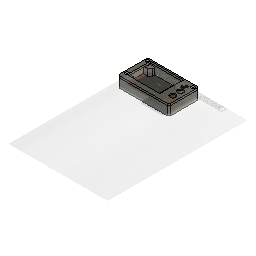
TFT screen (Autodesk Fusion 360 design; units mm, degrees)
part number: 2025-12-18-20-07-08-891
Autodesk Fusion 360 part; units mm, degrees
sketch "Sketch1" plane through (0, 0, 0) normal (0, 0, 1) x (1, 0, 0)
  line L0 (0, 0) -> (108, 0)
  line L1 (108, 0) -> (108, 63)
  line L2 (108, 63) -> (0, 63)
  line L3 (0, 63) -> (0, 0)
  line L4 (0, 0) -> (3, 0) construction
  line L5 (3, 0) -> (3, 3) construction
  line L6 (3, 3) -> (105, 3)
  line L7 (105, 3) -> (105, 60)
  line L8 (105, 60) -> (3, 60)
  line L9 (3, 60) -> (3, 3)
  line L10 (105, 60) -> (86, 60)
  line L11 (86, 60) -> (86, 3)
  line L12 (86, 3) -> (105, 3)
  line L13 (105, 3) -> (105, 60)
  line L14 (3, 60) -> (18, 60)
  line L15 (18, 60) -> (18, 3)
  line L16 (18, 3) -> (3, 3)
  line L17 (3, 3) -> (3, 60)
  line L18 (3, 60) -> (6, 60)
  line L19 (3, 60) -> (6, 60)
  line L20 (6, 60) -> (6, 57) construction
  circle A0 centre (6, 57) radius 1.6
  line L21 (3, 60) -> (3, 10) construction
  line L22 (3, 10) -> (6, 10) construction
  line L23 (6, 10) -> (6, 13) construction
  circle A1 centre (6, 13) radius 1.6
  line L24 (105, 60) -> (72.5, 60) construction
  line L25 (72.5, 60) -> (62.5, 60)
  line L26 (62.5, 60) -> (62.5, 38)
  line L27 (62.5, 38) -> (72.5, 38)
  line L28 (72.5, 38) -> (72.5, 60)
  line L29 (57.6, 60) -> (18, 60)
  line L30 (18, 60) -> (18, 3)
  line L31 (18, 3) -> (57.6, 3)
  line L32 (57.6, 3) -> (57.6, 60)
  dimension "d1" = 108
  dimension "d2" = 63
  dimension "d3" = 102
  dimension "d4" = 57
  dimension "d5" = 19
  dimension "d12" = 15
  dimension "d15" = 3.2
  dimension "d16" = 50
  dimension "d17" = 3
  dimension "d18" = 3
  dimension "d19" = 3.2
  dimension "d23" = 32.5
  dimension "d24" = 10
  dimension "d25" = 22
  constraint horizontal L0
  constraint vertical L1
  constraint horizontal L2
  constraint vertical L3
  constraint coincident L0.start L3.end
  constraint coincident L0 L4.end
  constraint perpendicular L4 L5
  constraint horizontal L6
  constraint vertical L7
  constraint horizontal L8
  constraint vertical L9
  constraint horizontal L10
  constraint vertical L11
  constraint horizontal L12
  constraint vertical L13
  constraint horizontal L14
  constraint vertical L15
  constraint horizontal L16
  constraint vertical L17
  constraint coincident L8 L18.end
  constraint perpendicular L8 L20
  constraint coincident L20.end A0.centre
  constraint perpendicular L8 L21
  constraint perpendicular L21 L22
  constraint perpendicular L22 L23
  constraint coincident L23.end A1.centre
  constraint perpendicular L11 L24
  constraint horizontal L25
  constraint vertical L26
  constraint horizontal L27
  constraint vertical L28
  constraint horizontal L29
  constraint vertical L30
  constraint horizontal L31
  constraint vertical L32
  constraint coincident L8 L29.start
  measures "d1" distance of L0.start L0.end
  measures "d2" distance of L0.start L2.end
  measures "d3" distance of L5.end L6.end
  measures "d4" distance of L5.end L8.end
  measures "d5" distance of L7.end L10.end
  measures "d12" distance of L8.end L14.end
  measures "d15" diameter of A0
  measures "d16" distance of L8.end L21.end
  measures "d17" distance of L21.end L22.end
  measures "d18" distance of L22.end L23.end
  measures "d19" diameter of A1
  measures "d23" distance of L7.end L24.end
  measures "d24" distance of L24.end L25.end
  measures "d25" distance of L24.end L27.end
extrude "Extrude1" add sketch "Sketch1" against normal blind 4 contours L0 L1 L2 L3 | L6 L8 L9 L14 L15 L16 L17 L18 L19 L30 | L6 L8 L15 L29 L30 L31 L32 | L6 L8 L11 L26 L27 L28 L32 | L6 L7 L8 L10 L11 L12 L13 | L8 L25 L26 L27 L28 | A0 | A1 makes body 1
extrude "Extrude2" add sketch "Sketch1" along normal blind 19 contours L0 L1 L2 L3 bodies 1
extrude "Extrude3" add sketch "Sketch1" along normal blind 6 contours L6 L7 L8 L10 L11 L12 L13 bodies 1
extrude "Extrude4" add sketch "Sketch1" along normal blind 12 contours L6 L8 L9 L14 L15 L16 L17 L18 L19 L30 | A0 | A1 bodies 1
extrude "Extrude5" cut sketch "Sketch1" along normal blind 3 from surface at 9 contours A0 | A1 bodies 1
extrude "Extrude6" cut sketch "Sketch1" against normal blind 2 contours L8 L25 L26 L27 L28 bodies 1
sketch "Sketch2" plane through (0, 60, 0) normal (0, -1, 0) x (1, 0, 0)
  line L0 (18, 12) -> (18, 0)
  line L1 (18, 0) -> (62.5, 0)
  line L2 (62.5, 0) -> (62.5, -2)
  line L3 (62.5, -2) -> (72.5, -2)
  line L4 (72.5, -2) -> (72.5, 0)
  line L5 (72.5, 0) -> (86, 0)
  line L6 (86, 0) -> (86, 6)
  line L7 (86, 6) -> (105, 6)
  line L8 (105, 6) -> (105, 19)
  line L9 (105, 19) -> (3, 19)
  line L10 (3, 19) -> (3, 12)
  line L11 (3, 12) -> (18, 12)
  line L12 (62.5, -2) -> (72.5, -2)
  line L13 (72.5, -2) -> (72.5, 2.5)
  line L14 (72.5, 2.5) -> (62.5, 2.5)
  line L15 (62.5, 2.5) -> (62.5, -2)
  point P0 (72.5, 0)
  dimension "d28" = 4.5
  constraint horizontal L12
  constraint vertical L13
  constraint horizontal L14
  constraint vertical L15
  constraint coincident L2.end L3.start
  constraint coincident P0 L13
  measures "d28" distance of L2.end L14.end
extrude "Extrude7" cut sketch "Sketch2" against normal blind 3 contours L2 L3 L4 L12 L13 L14 L15 bodies 1
fillet "Fillet1" radius 1 4 edges at (62.5, 61.5, 2.5) (72.5, 61.5, 2.5) (62.5, 50.5, -2) (72.5, 50.5, -2) on bodies 1
extrude "Extrude8" cut sketch "Sketch1" against normal blind 2 contours L6 L8 L15 L29 L30 L31 L32 bodies 1
fillet "Fillet2" radius 1 2 edges at (57.6, 31.5, 0) (57.6, 31.5, -2) on bodies 1
sketch "Sketch3" plane through (0, 0, 12) normal (0, 0, 1) x (-1, 0, 0)
  circle A0 centre (-6, -57) radius 1.6
  circle A1 centre (-6, -13) radius 1.6
  line L0 (-3, -3) -> (-18, -3)
  line L1 (-18, -3) -> (-18, -60)
  line L2 (-18, -60) -> (-3, -60)
  line L3 (-3, -60) -> (-3, -3)
  line L4 (-18, -20.2) -> (-3, -20.2)
  line L5 (-3, -20.2) -> (-3, -50.2)
  line L6 (-3, -50.2) -> (-18, -50.2)
  line L7 (-18, -50.2) -> (-18, -20.2)
  dimension "d37" = 30
  constraint horizontal L4
  constraint vertical L5
  constraint horizontal L6
  constraint vertical L7
  constraint coincident L1 L4.start
  measures "d37" distance of L4.start L6.end
extrude "Extrude9" cut sketch "Sketch3" against normal blind 14 contours L1 L3 L4 L5 L6 L7 bodies 1
chamfer "Chamfer1" distance 5 angle 45 2 edges at (18, 50.2, 5) (18, 20.2, 5) on bodies 1
chamfer "Chamfer2" distance 2 angle 45 1 edges at (86, 31.5, 6) on bodies 1
sketch "Sketch4" plane through (0, 0, 19) normal (0, 0, 1) x (-1, 0, 0)
  line L0 (-105, -60) -> (-105, -3)
  line L1 (-105, -3) -> (-3, -3)
  line L2 (-3, -3) -> (-3, -60)
  line L3 (-3, -60) -> (-105, -60)
  line L4 (0, -63) -> (0, 0)
  line L5 (0, 0) -> (-108, 0)
  line L6 (-108, 0) -> (-108, -63)
  line L7 (-108, -63) -> (0, -63)
  line L8 (-3, -60) -> (-9, -60)
  line L9 (-9, -60) -> (-78.5, -60)
  line L10 (-78.5, -60) -> (-78.5, -10)
  line L11 (-78.5, -10) -> (-9, -10)
  line L12 (-9, -10) -> (-9, -60)
  line L13 (-9, -60) -> (-3, -60)
  line L14 (-3, -60) -> (-3, -3)
  line L15 (-3, -3) -> (-9, -3)
  line L16 (-9, -3) -> (-9, -60)
  line L17 (-3, -9.5) -> (-3, -60)
  circle A0 centre (-6, -57) radius 1.6
  dimension "d42" = 6
  dimension "d43" = 69.5
  dimension "d81" = 50
  constraint coincident L2.end L3.start
  constraint perpendicular L2 L8
  constraint horizontal L9
  constraint vertical L10
  constraint horizontal L11
  constraint vertical L12
  constraint horizontal L13
  constraint vertical L14
  constraint horizontal L15
  constraint vertical L16
  constraint coincident L1.end L2.start
  constraint coincident L8 L2.end
  constraint vertical L17
  measures "d42" distance of L2.end L8.end
  measures "d43" distance of L8.end L9.end
  measures "d81" distance of L9.end L10.end
extrude "Extrude10" add sketch "Sketch4" against normal blind 2 separate body contours L0 L1 L3 L10 L11 L16 | L1 L2 L3 L8 L12 L13 L14 L15 L16 L17 | A0 makes body 2
extrude "Extrude11" add sketch "Sketch4" against normal blind 4 contours L1 L2 L3 L8 L12 L13 L14 L15 L16 L17 | A0 bodies 2
sketch "Sketch5" plane through (0, 0, 19) normal (0, 0, 1) x (-1, 0, 0)
  line L0 (-105, -60) -> (-105, -3)
  line L1 (-105, -3) -> (-3, -3)
  line L2 (-3, -3) -> (-3, -60)
  line L3 (-3, -60) -> (-105, -60)
  line L4 (0, -63) -> (0, 0)
  line L5 (0, 0) -> (-108, 0)
  line L6 (-108, 0) -> (-108, -63)
  line L7 (-108, -63) -> (0, -63)
  circle A0 centre (-6, -57) radius 1.8
  circle A1 centre (-6, -13) radius 1.8
  dimension "d49" = 3.6
  dimension "d50" = 3.6
  measures "d49" diameter of A0
  measures "d50" diameter of A1
extrude "Extrude12" cut sketch "Sketch5" against normal blind 4 contours A0 | A1 bodies 2
sketch "Sketch6" plane through (0, 0, 19) normal (0, 0, 1) x (-1, 0, 0)
  circle A0 centre (-6, -13) radius 1.8
  circle A1 centre (-6, -57) radius 1.8
  line L0 (-3, -3) -> (-105, -3)
  line L1 (-105, -3) -> (-105, -60)
  line L2 (-105, -60) -> (-78.5, -60)
  line L3 (-78.5, -60) -> (-78.5, -10)
  line L4 (-78.5, -10) -> (-9, -10)
  line L5 (-9, -10) -> (-9, -60)
  line L6 (-9, -60) -> (-3, -60)
  line L7 (-3, -60) -> (-3, -3)
  line L8 (-78.5, -60) -> (-80.5, -60)
  line L9 (-80.5, -60) -> (-80.5, -10)
  line L10 (-80.5, -10) -> (-78.5, -10)
  line L11 (-78.5, -10) -> (-78.5, -60)
  line L12 (-78.5, -10) -> (-96.5, -10) construction
  line L13 (-96.5, -10) -> (-96.5, -20) construction
  circle A2 centre (-96.5, -20) radius 6
  line L14 (-96.5, -20) -> (-96.5, -36.24) construction
  circle A3 centre (-96.5, -36.24) radius 6
  line L15 (-105, -60) -> (-105, -57) construction
  line L16 (-105, -57) -> (-102, -57) construction
  circle A4 centre (-102, -57) radius 1.8
  dimension "d53" = 2
  dimension "d56" = 18
  dimension "d57" = 10
  dimension "d58" = 12
  dimension "d60" = 12
  dimension "d63" = 3
  dimension "d64" = 3
  dimension "d65" = 3.6
  dimension "d82" = 23.76
  constraint horizontal L8
  constraint vertical L9
  constraint horizontal L10
  constraint vertical L11
  constraint coincident L2.end L3.start
  constraint perpendicular L9 L12
  constraint perpendicular L12 L13
  constraint coincident L13.end A2.centre
  constraint parallel L1 L14
  constraint coincident L14.end A3.centre
  constraint coincident L1.end L2.start
  constraint perpendicular L2 L15
  constraint perpendicular L1 L16
  constraint coincident L16.end A4.centre
  constraint collinear L4 L12
  measures "d53" distance of L2.end L8.end
  measures "d56" distance of L3.end L12.end
  measures "d57" distance of L12.end L13.end
  measures "d58" diameter of A2
  measures "d60" diameter of A3
  measures "d63" distance of L1.end L15.end
  measures "d64" distance of L15.end L16.end
  measures "d65" diameter of A4
  measures "d82" distance of L2 L14.end
extrude "Extrude13" add sketch "Sketch6" against normal blind 4 contours L2 L3 L8 L9 L10 L11 bodies 2
extrude "Extrude14" cut sketch "Sketch6" against normal blind 2 contours A2 | A3 bodies 2
extrude "Extrude15" cut sketch "Sketch6" against normal blind 2 contours A4 bodies 2
sketch "Sketch7" plane through (0, 0, 0) normal (0, -1, 0) x (1, 0, 0)
  line L0 (0, 19) -> (0, -4)
  line L1 (0, -4) -> (108, -4)
  line L2 (108, -4) -> (108, 19)
  line L3 (108, 19) -> (0, 19)
  line L4 (0, 19) -> (108, 19)
  line L5 (108, 19) -> (108, 15)
  line L6 (108, 15) -> (0, 15)
  line L7 (0, 15) -> (0, 19)
  dimension "d68" = 4
  constraint horizontal L4
  constraint vertical L5
  constraint horizontal L6
  constraint vertical L7
  constraint coincident L2 L5.end
  constraint coincident L0.start L3.end
  measures "d68" distance of L0.start L6.end
ref_plane "WorkPlane5" through (0, 0, 15) normal (0, 0, 1) x (1, 0, 0)
split "Split1" by plane through (0, 0, 15) normal (0, 0, 1) bodies 1 makes body 3 at (37, 62, 19)
combine "Combine1" operation add target body 2 tool bodies 3
chamfer "Chamfer3" distance 3 angle 45 8 edges at (0, 0, 5.5) (108, 0, 5.5) (108, 63, 5.5) (0, 63, 5.5) (0, 0, 17) (108, 0, 17) (108, 63, 17) (0, 63, 17) on bodies 1 2
sketch "Sketch8" plane through (0, 0, 19) normal (0, 0, 1) x (-1, 0, 0)
  line L0 (-3, -63) -> (0, -60)
  line L1 (0, -60) -> (0, -3)
  line L2 (0, -3) -> (-3, 0)
  line L3 (-3, 0) -> (-105, 0)
  line L4 (-105, 0) -> (-108, -3)
  line L5 (-108, -3) -> (-108, -60)
  line L6 (-108, -60) -> (-105, -63)
  line L7 (-105, -63) -> (-3, -63)
  circle A0 centre (-102, -57) radius 1.8
  circle A1 centre (-96.5, -36.24) radius 6
  circle A2 centre (-96.5, -20) radius 6
  line L8 (-78.5, -10) -> (-9, -10)
  line L9 (-9, -10) -> (-9, -60)
  line L10 (-9, -60) -> (-78.5, -60)
  line L11 (-78.5, -60) -> (-78.5, -10)
  circle A3 centre (-6, -13) radius 1.8
  circle A4 centre (-6, -57) radius 1.8
  line L12 (-96.1583, -52.9621) -> (-96.1583, -53.4734)
  line L13 (-96.1583, -53.4734) -> (-92.3324, -53.4734)
  line L14 (-92.3324, -53.4734) -> (-92.3324, -52.9611)
  line L15 (-92.3324, -52.9611) -> (-91.8652, -52.9611)
  line L16 (-91.8652, -52.9611) -> (-91.8652, -49.8846)
  line L17 (-91.8652, -49.8846) -> (-91.4, -49.8846)
  line L18 (-91.4, -49.8846) -> (-91.4, -49.4)
  line L19 (-91.4, -49.4) -> (-90.6974, -49.4)
  line L20 (-90.6974, -49.4) -> (-90.6974, -48.8836)
  line L21 (-90.6974, -48.8836) -> (-89.9409, -48.8836)
  line L22 (-89.9409, -48.8836) -> (-89.9409, -48.4774)
  line L23 (-89.9409, -48.4774) -> (-89.4202, -48.4774)
  line L24 (-89.4202, -48.4774) -> (-89.4202, -48)
  line L25 (-89.4202, -48) -> (-88.5692, -48)
  line L26 (-88.5692, -48) -> (-88.5692, -48.4999)
  line L27 (-88.5692, -48.4999) -> (-88.0506, -48.4999)
  line L28 (-88.0506, -48.4999) -> (-88.0506, -48.9532)
  line L29 (-88.0506, -48.9532) -> (-87.5536, -48.9532)
  line L30 (-87.5536, -48.9532) -> (-87.5536, -49.93)
  line L31 (-87.5536, -49.93) -> (-87.0506, -49.93)
  line L32 (-87.0506, -49.93) -> (-87.0506, -47.0569)
  line L33 (-87.0506, -47.0569) -> (-87.5536, -47.0569)
  line L34 (-87.5536, -47.0569) -> (-87.5536, -46.6)
  line L35 (-87.5536, -46.6) -> (-88.0438, -46.6)
  line L36 (-88.0438, -46.6) -> (-88.0438, -46.1079)
  line L37 (-88.0438, -46.1079) -> (-88.5459, -46.1079)
  line L38 (-88.5459, -46.1079) -> (-88.5459, -45.6213)
  line L39 (-88.5459, -45.6213) -> (-89, -45.6213)
  line L40 (-89, -45.6213) -> (-89, -45.1217)
  line L41 (-89, -45.1217) -> (-89.5072, -45.1217)
  line L42 (-89.5072, -45.1217) -> (-89.5072, -43.2591)
  line L43 (-89.5072, -43.2591) -> (-90.4, -43.2591)
  line L44 (-90.4, -43.2591) -> (-90.4, -43.745)
  line L45 (-90.4, -43.745) -> (-89.9536, -43.745)
  line L46 (-89.9536, -43.745) -> (-89.9536, -44.2)
  line L47 (-89.9536, -44.2) -> (-90.4, -44.2)
  line L48 (-90.4, -44.2) -> (-90.4, -44.6588)
  line L49 (-90.4, -44.6588) -> (-90.8859, -44.6588)
  line L50 (-90.8859, -44.6588) -> (-90.8859, -45.1236)
  line L51 (-90.8859, -45.1236) -> (-91.4, -45.1236)
  line L52 (-91.4, -45.1236) -> (-91.4, -44.6588)
  line L53 (-91.4, -44.6588) -> (-91.8, -44.6588)
  line L54 (-91.8, -44.6588) -> (-91.8, -43.2297)
  line L55 (-91.8, -43.2297) -> (-92.8, -43.2297)
  line L56 (-92.8, -43.2297) -> (-92.8, -43.7658)
  line L57 (-92.8, -43.7658) -> (-92.3255, -43.7658)
  line L58 (-92.3255, -43.7658) -> (-92.3, -45.6423)
  line L59 (-92.3, -45.6423) -> (-92.8, -45.6491)
  line L60 (-92.8, -45.6491) -> (-92.8, -46.1424)
  line L61 (-92.8, -46.1424) -> (-93.2962, -46.1424)
  line L62 (-93.2962, -46.1424) -> (-93.2962, -46.8)
  line L63 (-93.2962, -46.8) -> (-93.8, -46.8)
  line L64 (-93.8, -46.8) -> (-93.8, -48.5007)
  line L65 (-93.8, -48.5007) -> (-94.2, -48.5007)
  line L66 (-94.2, -48.5007) -> (-94.2, -48)
  line L67 (-94.2, -48) -> (-94.6826, -48)
  line L68 (-94.6826, -48) -> (-94.6826, -49)
  line L69 (-94.6826, -49) -> (-93.8, -49)
  line L70 (-93.8, -49) -> (-93.8, -49.9202)
  line L71 (-93.8, -49.9202) -> (-95.6517, -49.9202)
  line L72 (-95.6517, -49.9202) -> (-95.6517, -50.4)
  line L73 (-95.6517, -50.4) -> (-94.2576, -50.4)
  line L74 (-94.2576, -50.4) -> (-94.2576, -50.9095)
  line L75 (-94.2576, -50.9095) -> (-96.6, -50.9095)
  line L76 (-96.6, -50.9095) -> (-96.6, -52.9621)
  line L77 (-96.6, -52.9621) -> (-96.1583, -52.9621)
  constraint vertical L12
  constraint perpendicular L12 L13
  constraint perpendicular L13 L14
  constraint perpendicular L12 L15
  constraint perpendicular L15 L16
  constraint perpendicular L16 L17
  constraint perpendicular L17 L18
  constraint perpendicular L16 L19
  constraint perpendicular L19 L20
  constraint perpendicular L20 L21
  constraint perpendicular L21 L22
  constraint perpendicular L22 L23
  constraint perpendicular L23 L24
  constraint perpendicular L24 L25
  constraint perpendicular L25 L26
  constraint perpendicular L24 L27
  constraint perpendicular L27 L28
  constraint perpendicular L28 L29
  constraint perpendicular L29 L30
  constraint perpendicular L30 L31
  constraint perpendicular L31 L32
  constraint perpendicular L32 L33
  constraint perpendicular L33 L34
  constraint perpendicular L32 L35
  constraint perpendicular L35 L36
  constraint perpendicular L36 L37
  constraint perpendicular L35 L38
  constraint perpendicular L38 L39
  constraint perpendicular L37 L40
  constraint perpendicular L40 L41
  constraint perpendicular L41 L42
  constraint perpendicular L40 L43
  constraint perpendicular L41 L44
  constraint perpendicular L44 L45
  constraint perpendicular L45 L46
  constraint perpendicular L46 L47
  constraint perpendicular L45 L48
  constraint perpendicular L48 L49
  constraint perpendicular L49 L50
  constraint perpendicular L48 L51
  constraint perpendicular L51 L52
  constraint perpendicular L52 L53
  constraint perpendicular L53 L54
  constraint perpendicular L52 L55
  constraint perpendicular L53 L56
  constraint perpendicular L56 L57
  constraint perpendicular L58 L59
  constraint perpendicular L53 L60
  constraint perpendicular L60 L61
  constraint perpendicular L61 L62
  constraint perpendicular L60 L63
  constraint perpendicular L63 L64
  constraint perpendicular L64 L65
  constraint perpendicular L65 L66
  constraint perpendicular L64 L67
  constraint perpendicular L67 L68
  constraint perpendicular L68 L69
  constraint perpendicular L69 L70
  constraint perpendicular L70 L71
  constraint perpendicular L71 L72
  constraint perpendicular L72 L73
  constraint perpendicular L73 L74
  constraint perpendicular L74 L75
  constraint perpendicular L75 L76
  constraint perpendicular L12 L77
extrude "Extrude16" cut sketch "Sketch8" against normal blind 1 contours L12 L13 L14 L15 L16 L17 L18 L19 L20 L21 L22 L23 L24 L25 L26 L27 L28 L29 L30 L31 L32 L33 L34 L35 L36 L37 L38 L39 L40 L41 L42 L43 L44 L45 L46 L47 L48 L49 L50 L51 L52 L53 L54 L55 L56 L57 L58 L59 L60 L61 L62 L63 L64 L65 L66 L67 L68 L69 L70 L71 L72 L73 L74 L75 L76 L77 bodies 2
extrude "Extrude17" add 1 faces at (94.2494, 52.2775, 18) along direction (0, 0, 1) blind 1 separate body on bodies 2 makes body 4
copy_body "Body->Comp1" bodies 1 removing the originals makes body 5 in component "bottom"
copy_body "Body->Comp2" bodies 2 removing the originals makes body 6 in component "cover"
copy_body "CutPasteBodies1" bodies 4 removing the originals makes body 7 in component "cover"
copy_body "Body->Comp1'" bodies 6 removing the originals makes body 8 in component "Component"
copy_body "Body->Comp2'" bodies 7 removing the originals makes body 9 in component "dino"
chamfer "Chamfer1'" distance 1.7 angle 45 3 edges at (7.6782, 12.3491, 19) (7.6782, 56.3491, 19) (103.6782, 56.3491, 19) on bodies 8 in component "Component"
component "bottom" placed x (1, 0, 0) y (0, 1, 0) z (0, 0, 1) at (0, 0, 0)
component "cover" placed x (1, 0, 0) y (0, 1, 0) z (0, 0, 1) at (0, 0, 0)
component "Component" placed x (1, 0, 0) y (0, 1, 0) z (0, 0, 1) at (0, 0, 0) in component "cover"
component "dino" placed x (1, 0, 0) y (0, 1, 0) z (0, 0, 1) at (0, 0, 0) in component "cover"
equation "d82 = 27.76 mm - 4 mm"
named bodies: "dino"
